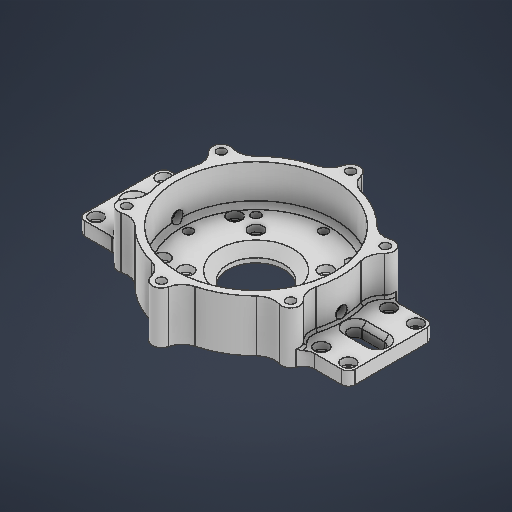
# Autodesk Inventor part: hou
Saved by Autodesk Inventor 2026.2 (Build 302298010, 298A)
## iProperties
Created: 2026-03-31
Part Number: hou
Material: 일반
Document SubType Name: Modeling
Designer: work
Density: 1 g/cm^3
Appearance: 기본값
Author: work
Autodesk Inventor part; units mm, degrees
ref_plane "YZ Plane" through (0, 0, 0) normal (1, 0, 0) x (0, 1, 0)
ref_plane "XZ Plane" through (0, 0, 0) normal (0, 1, 0) x (-1, 0, 0)
ref_plane "XY Plane" through (0, 0, 0) normal (0, 0, 1) x (1, 0, 0)
sketch "스케치1" plane through (0, 0, 0) normal (0, 1, 0) x (-1, 0, 0)
  circle A0 centre (0, 0) radius 30 construction
  circle A1 centre (0, -30) radius 1.55
  line L0 (0, -30) -> (0, 0) construction
  circle A2 centre (21.2132, -21.2132) radius 1.55
  circle A3 centre (30, 0) radius 1.55
  circle A4 centre (21.2132, 21.2132) radius 1.55
  circle A5 centre (0, 30) radius 1.55
  circle A6 centre (-21.2132, 21.2132) radius 1.55
  circle A7 centre (-30, 0) radius 1.55
  circle A8 centre (-21.2132, -21.2132) radius 1.55
  circle A9 centre (0, 0) radius 12.5
  line L1 (-15.5, 15.5) -> (15.5, 15.5) construction
  line L2 (15.5, 15.5) -> (15.5, -15.5) construction
  line L3 (15.5, -15.5) -> (-15.5, -15.5) construction
  line L4 (-15.5, -15.5) -> (-15.5, 15.5) construction
  line L5 (-15.5, 15.5) -> (15.5, -15.5) construction
  line L6 (15.5, 15.5) -> (-15.5, -15.5) construction
  circle A10 centre (15.5, 15.5) radius 2
  circle A11 centre (15.5, -15.5) radius 2
  circle A12 centre (-15.5, -15.5) radius 2
  circle A13 centre (-15.5, 15.5) radius 2
  circle A14 centre (0, 0) radius 35
  circle A15 centre (0, 0) radius 38
  line L7 (-25.5, 16) -> (25.5, 16) construction
  line L8 (25.5, 16) -> (25.5, -16) construction
  line L9 (25.5, -16) -> (-25.5, -16) construction
  line L10 (-25.5, -16) -> (-25.5, 16) construction
  line L11 (-25.5, 16) -> (25.5, -16) construction
  line L12 (25.5, 16) -> (-25.5, -16) construction
  circle A16 centre (-25.5, 16) radius 2
  circle A17 centre (-25.5, -16) radius 2
  circle A18 centre (25.5, -16) radius 2
  circle A19 centre (25.5, 16) radius 2
  dimension "d0" = 60
  dimension "d1" = 3.1
  dimension "d4" = 360
  dimension "d7" = 25
  dimension "d8" = 31
  dimension "d9" = 31
  dimension "d10" = 4
  dimension "d11" = 4
  dimension "d12" = 4
  dimension "d14" = 4
  dimension "d15" = 70
  dimension "d16" = 3
  dimension "d17" = 51
  dimension "d18" = 32
  dimension "d19" = 4
  dimension "d20" = 4
  dimension "d21" = 4
  dimension "d22" = 4
  constraints: 26 end point, 19 centre point, 11 coincident, 4 midpoint, 4 parallel, 2 horizontal, 2 perpendicular, 1 vertical, 1 vertical alignment, 20 other
  measures "d1" diameter of A1
  measures "d7" diameter of A9
  measures "d8" distance of L2.end L3.end
  measures "d9" distance of L1.end L2.end
  measures "d10" diameter of A10
  measures "d11" diameter of A11
  measures "d12" diameter of A12
  measures "d14" diameter of A13
  measures "d15" diameter of A14
  measures "d16" radial gap between concentric circles of A15 A14
  measures "d17" distance of L8.end L9.end
  measures "d18" distance of L7.end L8.end
  measures "d19" diameter of A16
  measures "d20" diameter of A17
  measures "d21" diameter of A18
  measures "d22" diameter of A19
extrude "돌출1" add sketch "스케치1" along normal blind 6 contours A14
extrude "돌출2" add sketch "스케치1" along normal blind 23 contours A15
extrude "돌출3" add sketch "스케치1" along normal up to surface (23 mm away) contours A1 | A2 | A3 | A4 | A5 | A6 | A7 | A8
sketch "스케치2" plane through (0, 6, 0) normal (0, 1, 0) x (1, 0, 0)
  circle A0 centre (0, 0) radius 12.5 projected
  circle A1 centre (-15.5, -15.5) radius 2 projected
  circle A2 centre (-15.5, 15.5) radius 2 projected
  circle A3 centre (15.5, 15.5) radius 2 projected
  circle A4 centre (15.5, -15.5) radius 2 projected
  circle A5 centre (25.5, 16) radius 2 projected
  circle A6 centre (-25.5, 16) radius 2 projected
  circle A7 centre (-25.5, -16) radius 2 projected
  circle A8 centre (25.5, -16) radius 2 projected
  circle A9 centre (-25.5, -16) radius 2 projected
  point P0 (-27.4491, -16.4483)
  point P1 (-26.7516, -17.56)
  constraints: 8 coincident
hole "구멍1" at (-25.5, 6, -16) at (-15.5, 6, -15.5) at (15.5, 6, -15.5) at (15.5, 6, 15.5) at (-15.5, 6, 15.5) at (-25.5, 6, 16) at (25.5, 6, 16) at (25.5, 6, -16) direction (0, -1, 0) diameter 4 end through all counterbore diameter 6.2 counterbore depth 3
sketch "스케치3" plane through (0, 23, 0) normal (0, 1, 0) x (1, 0, 0)
  circle A0 centre (0, 42) radius 4
  circle A1 centre (0, 0) radius 38 projected
  line L0 (0, 42) -> (0, 0) construction
  arc A2 (-9.6997, 36.7412) -> (-3.9139, 42.8254) centre (-11.7417, 44.4762) ccw
  arc A3 (3.9139, 42.8254) -> (9.6997, 36.7412) centre (11.7417, 44.4762) ccw
  point P0 (9.6997, 36.7412)
  point P1 (3.9139, 42.8254)
  dimension "d38" = 8
  dimension "d39" = 8
  constraints: 4 point on circle, 3 symmetric about line, 2 centre point, 2 end point, 1 vertical, 8 other
  measures "d39" radius of A2
extrude "돌출4" add sketch "스케치3" against normal up to surface (23 mm away) contours A0 | A0 A3 A1 | A1 A2 A0
sketch "스케치4" plane through (0, 23, 0) normal (0, 1, 0) x (1, 0, 0)
  arc A0 (3.9139, 42.8254) -> (-3.9139, 42.8254) centre (0, 42) ccw projected
  point P0 (0, 0)
  constraints: 1 coincident
hole "구멍2" at (0, 23, -42) direction (0, -1, 0) diameter 4 end through all
fillet "모깎기3" radius 2 1 edges at (35, 6, 0)
pattern_circular "원형 패턴1" count 6 over 360 about axis through (0, 0, 0) along (0, 1, 0) of "돌출4", "구멍2"
sketch "스케치5" plane through (0, 0, 0) normal (0, -1, 0) x (1, 0, 0)
  arc A0 (-28.5512, 16.5477) -> (-28.5512, -16.5477) centre (0, 0) ccw projected
  circle A1 centre (-21.2132, 21.2132) radius 1.55 projected
  arc A2 (-27.3206, -18.5091) -> (27.3206, -18.5091) centre (0, 0) ccw projected
  arc A3 (-28.5512, 16.5477) -> (-27.3206, 18.5091) centre (-25.5, 16) ccw projected
  arc A4 (28.5512, -16.5477) -> (28.5512, 16.5477) centre (0, 0) ccw projected
  circle A5 centre (0, 30) radius 1.55 projected
  arc A6 (27.3206, 18.5091) -> (-27.3206, 18.5091) centre (0, 0) ccw projected
  circle A7 centre (21.2132, 21.2132) radius 1.55 projected
  circle A8 centre (30, 0) radius 1.55 projected
  arc A9 (27.3206, 18.5091) -> (28.5512, 16.5477) centre (25.5, 16) ccw projected
  circle A10 centre (21.2132, -21.2132) radius 1.55 projected
  arc A11 (28.5512, -16.5477) -> (27.3206, -18.5091) centre (25.5, -16) ccw projected
  circle A12 centre (0, -30) radius 1.55 projected
  circle A13 centre (-21.2132, -21.2132) radius 1.55 projected
  arc A14 (-27.3206, -18.5091) -> (-28.5512, -16.5477) centre (-25.5, -16) ccw projected
  circle A15 centre (-30, 0) radius 1.55 projected
  circle A16 centre (-15.5, 15.5) radius 3.1 projected
  circle A17 centre (15.5, 15.5) radius 3.1 projected
  circle A18 centre (15.5, -15.5) radius 3.1 projected
  circle A19 centre (-15.5, -15.5) radius 3.1 projected
  circle A20 centre (0, 0) radius 12.5 projected
  point P0 (28.5317, -9.2705)
  point P1 (17.6336, -24.2705)
  point P2 (-30, 0)
  point P3 (0, 30)
  point P4 (30, 0)
  constraints: 8 coincident
hole "구멍3" at (17.6336, 0, -24.2705) at (0, 0, -30) at (-21.2132, 0, -21.2132) at (-30, 0, 0) at (-21.2132, 0, 21.2132) at (0, 0, 30) at (21.2132, 0, 21.2132) at (30, 0, 0) direction (0, 1, 0) diameter 4 end through all counterbore diameter 6.2 counterbore depth 3
sketch "스케치6" plane through (0, 0, 0) normal (0, -1, 0) x (1, 0, 0)
  line L0 (44, -15) -> (56, -15) construction
  line L1 (56, -15) -> (56, 15) construction
  line L2 (56, 15) -> (44, 15) construction
  line L3 (44, 15) -> (44, -15) construction
  line L4 (44, -15) -> (56, 15) construction
  line L5 (56, -15) -> (44, 15) construction
  line L6 (0, 0) -> (50, 0) construction
  line L7 (34, 19) -> (60, 19)
  line L8 (60, 19) -> (60, -19)
  line L9 (60, -19) -> (34, -19)
  line L10 (34, -19) -> (34, 19)
  line L11 (44, 0) -> (54, 0) construction
  line L12 (44, -3) -> (54, -3)
  line L13 (54, 3) -> (44, 3)
  arc A0 (44, 3) -> (44, -3) centre (44, 0) ccw
  arc A1 (54, -3) -> (54, 3) centre (54, 0) ccw
  point P0 (50, 15)
  point P1 (50, -15)
  point P2 (49, 0)
  point P3 (57, 0)
  point P4 (60, 0)
  dimension "d60" = 12
  dimension "d61" = 30
  dimension "d62" = 50
  dimension "d63" = 10
  dimension "d64" = 4
  dimension "d65" = 4
  dimension "d66" = 4
  dimension "d67" = 6
  dimension "d68" = 10
  dimension "d69" = 3
  constraints: 30 end point, 6 midpoint, 5 parallel, 5 point on circle, 4 coincident, 4 tangent, 3 horizontal, 2 centre point, 2 perpendicular, 2 point on line
  measures "d60" distance of L0.start L0.end
  measures "d61" distance of L0.end L1.end
  measures "d62" distance of L6.start L6.end
  measures "d63" distance between parallel lines of L10 L3
  measures "d64" distance from line of L7 point (50, 15)
  measures "d65" distance from line of L9 point (50, -15)
  measures "d66" distance between parallel lines of L8 L1
  measures "d67" diameter of A1
  measures "d68" distance of L11.end L11.start
  measures "d69" distance of point (57, 0) point (60, 0)
extrude "돌출5" add sketch "스케치6" against normal blind 6
fillet "모깎기4" radius 3 2 edges at (60, 3, 19) (60, 3, -19)
sketch "스케치7" plane through (0, 6, 0) normal (0, 1, 0) x (1, 0, 0)
  line L0 (44, -15) -> (56, -15) construction
  line L1 (56, -15) -> (56, 15) construction
  line L2 (56, 15) -> (44, 15) construction
  line L3 (44, 15) -> (44, -15) construction
  line L4 (44, -15) -> (56, 15) construction
  line L5 (56, -15) -> (44, 15) construction
  line L6 (50, 0) -> (0, 0) construction
  dimension "d73" = 12
  dimension "d74" = 30
  dimension "d75" = 50
  constraints: 14 end point, 4 coincident, 2 horizontal, 2 midpoint, 2 parallel, 1 perpendicular
  measures "d73" distance of L2.end L1.end
  measures "d74" distance of L1.end L0.end
  measures "d75" distance of L6.end L6.start
hole "구멍4" at (44, 6, -15) at (56, 6, -15) at (44, 6, 15) at (56, 6, 15) direction (0, -1, 0) diameter 4 end through all counterbore diameter 6.1 counterbore depth 3
chamfer "모따기1" distance 2 angle 45 4 edges at (49, 6, -3) (57, 6, 0) (49, 6, 3) (41, 6, 0)
mirror "미러1" about plane through (0, 0, 0) normal (1, 0, 0) of "돌출5", "모깎기4", "구멍4", "모따기1"
fillet "모깎기5" radius 5 4 edges at (39.8372, 3, 19) (39.8372, 3, -19) (-39.8372, 3, -19) (-39.8372, 3, 19)
fillet "모깎기6" radius 1 14 edges at (40.3562, 6, -20.633) (39.4796, 6, -18.4802) (38, 6, 0) (36.7155, 6, 14.3336) (40.3562, 6, 20.633) (39.4796, 6, 18.4802) (36.7155, 6, -14.3336) (-36.7155, 6, 14.3336) (-40.3562, 6, 20.633) (-39.4796, 6, 18.4802) (-36.7155, 6, -14.3336) (-40.3562, 6, -20.633) (-39.4796, 6, -18.4802) (-38, 6, 0)
chamfer "모따기2" distance 4 angle 45 1 edges at (12.5, 6, 0)
sketch "스케치8" plane through (0, 0, 0) normal (1, 0, 0) x (0, 1, 0)
  line L0 (6, -12.4) -> (6, -18.6) projected
  line L1 (6, -12.4) -> (6, -18.6) projected
  line L2 (6, 18.6) -> (6, 12.4) projected
  line L3 (6, 18.6) -> (6, 12.4) projected
  line L4 (6, 18.5091) -> (6, 18.5091) projected
  line L5 (6, 18.5091) -> (6, 16.5477) projected
  line L6 (6, -16.5477) -> (6, 16.5477) projected
  line L7 (6, -16.5477) -> (6, -18.5091) projected
  line L8 (6, -18.5091) -> (6, -18.5091) projected
  line L9 (6, -18.5091) -> (6, -16.5477) projected
  line L10 (6, 16.5477) -> (6, -16.5477) projected
  line L11 (6, 16.5477) -> (6, 18.5091) projected
  line L12 (6, -22.2705) -> (6, -26.2705) projected
  line L13 (6, -28) -> (6, -32) projected
  line L14 (6, -19.2132) -> (6, -23.2132) projected
  line L15 (6, 2) -> (6, -2) projected
  line L16 (6, 23.2132) -> (6, 19.2132) projected
  line L17 (6, 32) -> (6, 28) projected
  line L18 (6, 23.2132) -> (6, 19.2132) projected
  line L19 (6, 2) -> (6, -2) projected
  line L20 (6, -16.5) -> (6, 16.5) projected
  line L21 (6, 0) -> (9, 0) construction
  circle A0 centre (9, 0) radius 2.5
  point P0 (0, 0)
  point P1 (6, -19.2132)
  point P2 (6, -23.2132)
  point P3 (6, -7.2705)
  point P4 (6, -11.2705)
  dimension "d91" = 3
  dimension "d92" = 5
  constraints: 2 end point, 1 centre point, 1 coincident, 1 horizontal, 1 midpoint
  measures "d91" distance of L21.start L21.end
  measures "d92" diameter of A0
extrude "돌출6" cut sketch "스케치8" along normal through all both and the other way through all
sketch "스케치9" plane through (21.2132, 23, -21.2132) normal (0, 1, 0) x (1, 0, 0)
  circle A0 centre (0, 0) radius 1.55 projected
  point P0 (-21.2132, -21.2132)
extrude "돌출7" cut sketch "스케치9" against normal up to surface (17 mm away)
